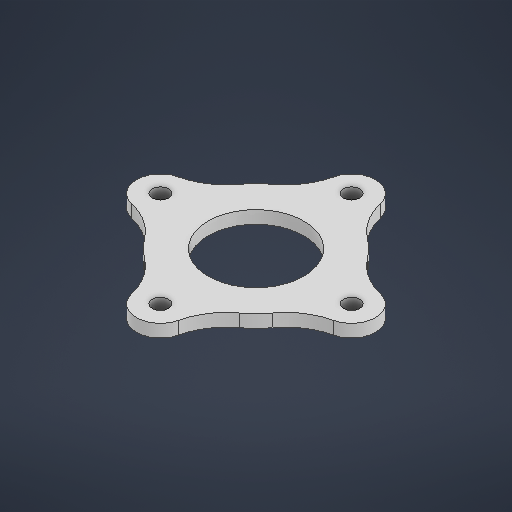
# Autodesk Inventor part: bearing_lock_middleplate_upper
Saved by Autodesk Inventor 2027.1 (Build 311270010, 270A)
## iProperties
Created: 2026-10-09
Part Number: bearing_lock_middleplate_upper
Material: Generic
Document SubType Name: Modeling
Designer: lucao
Density: 1 g/cm^3
Appearance: Default
Author: lucao
## iProperties of the stored document bearing_lock_middleplate_upper_3DPrint.ipt
Created: 2026-10-13
Part Number: bearing_lock_middleplate_upper_3DPrint
Material: Generic
Document SubType Name: Modeling
Designer: lucao
Density: 1 g/cm^3
Appearance: Default
Author: lucao
Autodesk Inventor part; units mm, degrees
ref_plane "YZ Plane" through (0, 0, 0) normal (1, 0, 0) x (0, 1, 0)
ref_plane "XZ Plane" through (0, 0, 0) normal (0, 1, 0) x (-1, 0, 0)
ref_plane "XY Plane" through (0, 0, 0) normal (0, 0, 1) x (1, 0, 0)
sketch "Sketch1" plane through (0, 0, 0) normal (0, 1, 0) x (-1, 0, 0)
  circle A0 centre (0, 0) radius 25
  circle A1 centre (0, 0) radius 15
  dimension "d0" = 50
  dimension "d1" = 30
  constraints: 2 centre point, 2 coincident
  measures "d0" diameter of A0
  measures "d1" diameter of A1
extrude "Extrusion1" add sketch "Sketch1" along normal blind 4
sketch "Sketch2" plane through (0, 4, 0) normal (0, 1, 0) x (1, 0, 0)
  circle A0 centre (0, 0) radius 25 projected
  circle A1 centre (0, 0) radius 15 projected
  circle A2 centre (0, -30) radius 2.55
  circle A3 centre (0, -30) radius 7.5
  arc A4 (-7.3103, -31.6761) -> (-14.8914, -20.081) centre (-26.8045, -36.1458) ccw
  arc A5 (14.8914, -20.081) -> (7.3103, -31.6761) centre (26.8045, -36.1458) ccw
  dimension "d4" = 5.1
  dimension "d5" = 30
  dimension "d6" = 15
  dimension "d7" = 20
  dimension "d8" = 20
  constraints: 8 point on circle, 4 centre point, 4 tangent, 1 coincident, 1 vertical alignment
  measures "d4" diameter of A2
  measures "d5" distance of point (0, 0) A2.centre
  measures "d6" diameter of A3
  measures "d7" radius of A4
  measures "d8" radius of A5
extrude "Extrusion2" add sketch "Sketch2" against normal up to surface (4 mm away) contours A0 A3 A4 | A5 A3 A0 | A0 A3 picked at (2.8959, -25.9101)
pattern_circular "Circular Pattern1" count 4 over 360 about axis through (0, 0, 0) along (0, 1, 0) of "Extrusion2"
body "Solid1"
